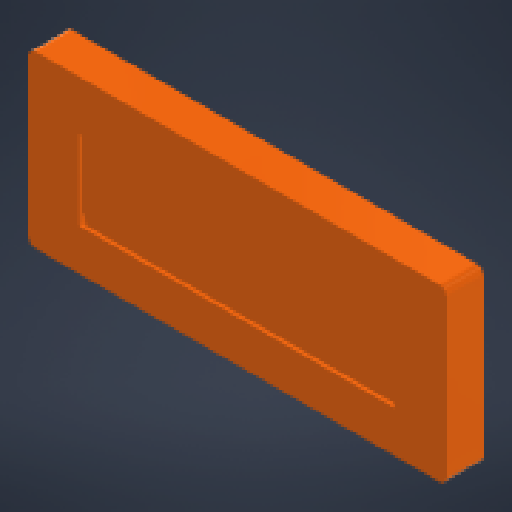
# Autodesk Inventor part: VFD_FRONT
Saved by Autodesk Inventor 2024.3 (Build 283343000, 343)
## iProperties
Created: 2026-11-11
Part Number: VFD_FRONT
Material: Generic
Document SubType Name: Modeling
Designer: REMOTE
Density: 1 g/cm^3
Appearance: Smooth - Light Orange
Author: REMOTE
Autodesk Inventor part; units mm, degrees
ref_plane "YZ Plane" through (0, 0, 0) normal (1, 0, 0) x (0, 1, 0)
ref_plane "XZ Plane" through (0, 0, 0) normal (0, 1, 0) x (-1, 0, 0)
sketch "Sketch1" plane through (0, 0, 0) normal (0, 0, 1) x (1, 0, 0)
  line L0 (-107.5, 42.5) -> (-107.5, -42.5) projected
  line L1 (107.5, 42.5) -> (-107.5, 42.5) projected
  line L2 (107.5, -42.5) -> (107.5, 42.5) projected
  line L3 (-107.5, -42.5) -> (107.5, -42.5) projected
  line L4 (-107.9, 42.9) -> (-107.9, -42.9)
  line L5 (-107.9, -42.9) -> (107.9, -42.9)
  line L6 (107.9, -42.9) -> (107.9, 42.9)
  line L7 (107.9, 42.9) -> (-107.9, 42.9)
  line L8 (-109.9, -44.9) -> (-109.9, 44.9)
  line L9 (-109.9, 44.9) -> (109.9, 44.9)
  line L10 (109.9, 44.9) -> (109.9, -44.9)
  line L11 (109.9, -44.9) -> (-109.9, -44.9)
  point P0 (0, 0)
  dimension "d0" = 0.4
  dimension "d1" = 2
  constraints: 16 end point, 6 other
  measures "d0" distance between parallel lines of L1 L7
  measures "d1" distance between parallel lines of L4 L8
extrude "Extrusion1" add sketch "Sketch1" along normal blind 15.5 contours L8 L9 L10 L11
sketch "Sketch2" plane through (0, 0, 15.5) normal (0, 0, 1) x (1, 0, 0)
  line L0 (81.5, 18) -> (81.5, -22) projected
  line L1 (-82.5, 18) -> (81.5, 18) projected
  line L2 (-82.5, -22) -> (-82.5, 18) projected
  line L3 (81.5, -22) -> (-82.5, -22) projected
  line L4 (-83.5, 19) -> (82.5, 19)
  line L5 (82.5, 19) -> (82.5, -23)
  line L6 (82.5, -23) -> (-83.5, -23)
  line L7 (-83.5, -23) -> (-83.5, 19)
  line L8 (-109.9, 44.9) -> (-109.9, -44.9) projected
  line L9 (109.9, 44.9) -> (-109.9, 44.9) projected
  line L10 (109.9, -44.9) -> (109.9, 44.9) projected
  line L11 (-109.9, -44.9) -> (109.9, -44.9) projected
  point P0 (0, 0)
  dimension "d4" = 1
  constraints: 8 end point, 3 other
  measures "d4" distance between parallel lines of L2 L7
extrude "Extrusion2" add sketch "Sketch2" along normal blind 2 contours L9 L10 L11 L8
fillet "Fillet1" radius 4 4 edges at (-109.9, -44.9, 8.75) (-109.9, 44.9, 8.75) (109.9, 44.9, 8.75) (109.9, -44.9, 8.75)
sketch "Sketch3" plane through (0, 0, 15.5) normal (0, 0, -1) x (-1, 0, 0)
  circle A0 centre (102.5, -37.5) radius 1.75 projected
  circle A1 centre (102.5, 37.5) radius 1.75 projected
  circle A2 centre (-102.5, -37.5) radius 1.75 projected
  line L0 (107, 20.25) -> (107, -20.25) projected
  line L1 (107, -20.25) -> (98.5, -20.25) projected
  line L2 (98.5, -20.25) -> (98.5, 20.25) projected
  circle A3 centre (-102.5, 37.5) radius 1.75 projected
  line L3 (-107.9, -42.9) -> (107.9, -42.9) projected
  line L4 (107.9, -42.9) -> (107.9, 42.9) projected
  line L5 (97.1, -32.1) -> (107.9, -32.1)
  line L6 (107.9, -32.1) -> (107.9, -42.9)
  line L7 (107.9, -42.9) -> (97.1, -42.9)
  line L8 (97.1, -42.9) -> (97.1, -32.1)
  line L9 (97.1, -32.1) -> (107.9, -42.9) construction
  line L10 (107.9, -32.1) -> (97.1, -42.9) construction
  line L11 (107.9, 42.9) -> (-107.9, 42.9) projected
  line L12 (97.1, 32.1) -> (107.9, 32.1)
  line L13 (107.9, 32.1) -> (107.9, 42.9)
  line L14 (107.9, 42.9) -> (97.1, 42.9)
  line L15 (97.1, 42.9) -> (97.1, 32.1)
  line L16 (97.1, 32.1) -> (107.9, 42.9) construction
  line L17 (107.9, 32.1) -> (97.1, 42.9) construction
  line L18 (-97.1, 32.1) -> (-107.9, 32.1)
  line L19 (-107.9, 32.1) -> (-107.9, 42.9)
  line L20 (-107.9, 42.9) -> (-97.1, 42.9)
  line L21 (-97.1, 42.9) -> (-97.1, 32.1)
  line L22 (-97.1, 32.1) -> (-107.9, 42.9) construction
  line L23 (-107.9, 32.1) -> (-97.1, 42.9) construction
  line L24 (-97.1, -32.1) -> (-107.9, -32.1)
  line L25 (-107.9, -32.1) -> (-107.9, -42.9)
  line L26 (-107.9, -42.9) -> (-97.1, -42.9)
  line L27 (-97.1, -42.9) -> (-97.1, -32.1)
  line L28 (-97.1, -32.1) -> (-107.9, -42.9) construction
  line L29 (-107.9, -32.1) -> (-97.1, -42.9) construction
  point P0 (0, 0)
  constraints: 48 end point, 8 midpoint, 8 parallel, 4 horizontal, 4 perpendicular
ref_plane "Work Plane1" through (-107.5, -42.5, 0) normal (0, 0, 1) x (1, 0, 0)
extrude "Extrusion4" add sketch "Sketch3" along normal blind 15.5
fillet "Fillet2" radius 6 12 edges at (107.9, 32.1, 7.75) (97.1, 42.9, 7.75) (97.1, 32.1, 7.75) (107.9, -32.1, 7.75) (97.1, -32.1, 7.75) (97.1, -42.9, 7.75) (-97.1, 42.9, 7.75) (-107.9, 32.1, 7.75) (-97.1, 32.1, 7.75) (-97.1, -42.9, 7.75) (-97.1, -32.1, 7.75) (-107.9, -32.1, 7.75)
sketch "Sketch4" plane through (0, 0, 0) normal (0, 0, -1) x (-1, 0, 0)
  circle A0 centre (-102.5, -37.5) radius 1.75 projected
  circle A1 centre (102.5, 37.5) radius 1.75 projected
  circle A2 centre (-102.5, 37.5) radius 1.75 projected
  circle A3 centre (102.5, -37.5) radius 1.75 projected
  arc A4 (-109.9, -40.9) -> (-105.9, -44.9) centre (-105.9, -40.9) ccw projected
  line L0 (105.9, -44.9) -> (-105.9, -44.9) projected
  arc A5 (105.9, -44.9) -> (109.9, -40.9) centre (105.9, -40.9) ccw projected
  line L1 (109.9, 40.9) -> (109.9, -40.9) projected
  arc A6 (109.9, 40.9) -> (105.9, 44.9) centre (105.9, 40.9) ccw projected
  line L2 (-105.9, 44.9) -> (105.9, 44.9) projected
  arc A7 (-105.9, 44.9) -> (-109.9, 40.9) centre (-105.9, 40.9) ccw projected
  line L3 (-109.9, -40.9) -> (-109.9, 40.9) projected
  arc A8 (102.4699, -32.1271) -> (97.0699, -37.5) centre (103.0398, -38.1) ccw projected
  arc A9 (91.1, -42.9) -> (97.0699, -37.5) centre (91.1, -36.9) ccw projected
  line L4 (-91.1543, -42.9) -> (91.1, -42.9) projected
  arc A10 (-97.1271, -37.4699) -> (-91.1543, -42.9) centre (-91.1543, -36.9) ccw projected
  arc A11 (-97.1271, -37.4699) -> (-102.5, -32.0699) centre (-103.1, -38.0398) ccw projected
  arc A12 (-107.9, -26.1) -> (-102.5, -32.0699) centre (-101.9, -26.1) ccw projected
  line L5 (-107.9, 26.1) -> (-107.9, -26.1) projected
  arc A13 (-102.4726, 32.0726) -> (-107.9, 26.1) centre (-101.9, 26.1) ccw projected
  arc A14 (-102.4726, 32.0726) -> (-97.0726, 37.4726) centre (-103.0452, 38.0452) ccw projected
  arc A15 (-91.1, 42.9) -> (-97.0726, 37.4726) centre (-91.1, 36.9) ccw projected
  line L6 (91.1, 42.9) -> (-91.1, 42.9) projected
  arc A16 (97.0726, 37.4726) -> (91.1, 42.9) centre (91.1, 36.9) ccw projected
  arc A17 (97.0726, 37.4726) -> (102.4726, 32.0726) centre (103.0452, 38.0452) ccw projected
  arc A18 (107.9, 26.1) -> (102.4726, 32.0726) centre (101.9, 26.1) ccw projected
  line L7 (107.9, -26.1543) -> (107.9, 26.1) projected
  arc A19 (102.4699, -32.1271) -> (107.9, -26.1543) centre (101.9, -26.1543) ccw projected
  arc A20 (105.9, -43.4) -> (108.4, -40.9) centre (105.9, -40.9) ccw
  line L8 (105.9, -43.4) -> (-105.9, -43.4)
  arc A21 (-108.4, -40.9) -> (-105.9, -43.4) centre (-105.9, -40.9) ccw
  line L9 (-108.4, -40.9) -> (-108.4, 40.9)
  arc A22 (-105.9, 43.4) -> (-108.4, 40.9) centre (-105.9, 40.9) ccw
  line L10 (-105.9, 43.4) -> (105.9, 43.4)
  arc A23 (108.4, 40.9) -> (105.9, 43.4) centre (105.9, 40.9) ccw
  line L11 (108.4, 40.9) -> (108.4, -40.9)
  point P0 (0, 0)
  point P1 (91.1, -42.9)
  point P2 (-107.9, -26.1)
  point P3 (-91.1, 42.9)
  point P4 (107.9, 26.1)
  dimension "d13" = 1.5
  constraints: 8 end point, 8 point on circle, 4 centre point, 7 other
  measures "d13" radial gap between concentric circles of A5 A20
extrude "Extrusion6" add sketch "Sketch4" along normal blind 2 contours L3 A7 L2 A6 L1 A5 L0 A4
body "Solid1"
